Lid (Autodesk Fusion 360 design; units mm, degrees)
Autodesk Fusion 360 part; units mm, degrees
sketch "Sketch1" plane through (0, 0, 0) normal (0, 1, 0) x (1, 0, 0)
  line L0 (15.425, -22.7) -> (-15.425, -22.7)
  line L1 (-15.425, -22.7) -> (-15.425, 22.7)
  line L2 (-15.425, 22.7) -> (15.425, 22.7)
  line L3 (15.425, 22.7) -> (15.425, -22.7)
  line L4 (15.425, -22.7) -> (-15.425, 22.7) construction
  line L5 (-15.425, -22.7) -> (15.425, 22.7) construction
  line L6 (2, 18.7) -> (-2, 18.7)
  line L7 (-2, 18.7) -> (-2, 26.7)
  line L8 (-2, 26.7) -> (2, 26.7)
  line L9 (2, 26.7) -> (2, 18.7)
  line L10 (2, 18.7) -> (-2, 26.7) construction
  line L11 (-2, 18.7) -> (2, 26.7) construction
  line L12 (2, -26.7) -> (-2, -26.7)
  line L13 (-2, -26.7) -> (-2, -18.7)
  line L14 (-2, -18.7) -> (2, -18.7)
  line L15 (2, -18.7) -> (2, -26.7)
  line L16 (2, -26.7) -> (-2, -18.7) construction
  line L17 (-2, -26.7) -> (2, -18.7) construction
  point P0 (0, 22.7)
  point P1 (0, -22.7)
  dimension "d1" = 30.85
  dimension "d2" = 45.4
  dimension "d3" = 4
  dimension "d4" = 8
  dimension "d5" = 8
  dimension "d6" = 4
  constraint perpendicular L0 L1
  constraint parallel L0 L2
  constraint parallel L1 L3
  constraint horizontal L0
  constraint coincident L4 origin
  constraint coincident L5 origin
  constraint perpendicular L6 L7
  constraint parallel L6 L8
  constraint parallel L7 L9
  constraint horizontal L6
  constraint coincident L10 P0
  constraint coincident L11 P0
  constraint midpoint L2 P0
  constraint perpendicular L12 L13
  constraint parallel L12 L14
  constraint parallel L13 L15
  constraint horizontal L12
  constraint coincident L16 P1
  constraint coincident L17 P1
  constraint midpoint L0 P1
  measures "d1" distance of L1.end L2.end
  measures "d2" distance of L0.end L2.start L1
  measures "d3" distance of L7.end L8.end
  measures "d4" distance of L6.end L7.end
  measures "d5" distance of L12.end L13.end
  measures "d6" distance of L13.end L14.end
extrude "Extrude1" add sketch "Sketch1" along normal blind 3
sketch "Sketch2" plane through (0, 3, 0) normal (0, 1, 0) x (-1, 0, 0)
  line L0 (-15.425, 22.7) -> (-15.425, -22.7)
  line L1 (-15.425, -22.7) -> (-2, -22.7)
  line L2 (-2, -22.7) -> (-2, -26.7)
  line L3 (-2, -26.7) -> (2, -26.7)
  line L4 (2, -26.7) -> (2, -22.7)
  line L5 (2, -22.7) -> (15.425, -22.7)
  line L6 (15.425, -22.7) -> (15.425, 22.7)
  line L7 (15.425, 22.7) -> (2, 22.7)
  line L8 (2, 22.7) -> (2, 26.7)
  line L9 (2, 26.7) -> (-2, 26.7)
  line L10 (-2, 26.7) -> (-2, 22.7)
  line L11 (-2, 22.7) -> (-15.425, 22.7)
  line L12 (2, 24.7) -> (-12.6116, 24.7) construction
  line L13 (2, -24.7) -> (-12.7099, -24.7) construction
  line L14 (0, -26.7) -> (0, -20.5021) construction
  line L15 (0, 26.7) -> (0, 22.5765) construction
  circle A0 centre (0, 24.7) radius 1.375
  circle A1 centre (0, -24.7) radius 1.375
  dimension "d9" = 2.75
  dimension "d10" = 2.75
  constraint midpoint L8 L12.start
  constraint perpendicular L8 L12
  constraint midpoint L4 L13.start
  constraint perpendicular L4 L13
  constraint midpoint L3 L14.start
  constraint perpendicular L3 L14
  constraint midpoint L9 L15.start
  constraint perpendicular L12 L15
  constraint coincident L15 A0.centre
  constraint coincident L12 A0.centre
  constraint coincident L14 A1.centre
  constraint coincident L13 A1.centre
  measures "d9" diameter of A0
  measures "d10" diameter of A1
extrude "Extrude2" cut sketch "Sketch2" against normal up to surface (3 mm away) contours A0 | A1
fillet "Fillet1" radius 2.5 4 edges at (-15.425, 1.5, 22.7) (15.425, 1.5, 22.7) (15.425, 1.5, -22.7) (-15.425, 1.5, -22.7)
sketch "Sketch3" plane through (0, 3, 0) normal (0, 1, 0) x (-1, 0, 0)
  arc A0 (12.925, -22.7) -> (15.425, -20.2) centre (12.925, -20.2) ccw
  line L0 (15.425, -20.2) -> (15.425, 20.2)
  arc A1 (15.425, 20.2) -> (12.925, 22.7) centre (12.925, 20.2) ccw
  line L1 (12.925, 22.7) -> (2, 22.7)
  line L2 (2, 22.7) -> (2, 26.7)
  line L3 (2, 26.7) -> (-2, 26.7)
  line L4 (-2, 26.7) -> (-2, 22.7)
  line L5 (-2, 22.7) -> (-12.925, 22.7)
  arc A2 (-12.925, 22.7) -> (-15.425, 20.2) centre (-12.925, 20.2) ccw
  line L6 (-15.425, 20.2) -> (-15.425, -20.2)
  arc A3 (-15.425, -20.2) -> (-12.925, -22.7) centre (-12.925, -20.2) ccw
  line L7 (-12.925, -22.7) -> (-2, -22.7)
  line L8 (-2, -22.7) -> (-2, -26.7)
  line L9 (-2, -26.7) -> (2, -26.7)
  line L10 (2, -26.7) -> (2, -22.7)
  line L11 (2, -22.7) -> (12.925, -22.7)
  circle A4 centre (0, -24.7) radius 1.375
  circle A5 centre (0, 24.7) radius 1.375
  line L12 (-13.675, 21.2) -> (13.675, 21.2)
  line L13 (13.675, 21.2) -> (13.675, -21.2)
  line L14 (13.675, -21.2) -> (-13.675, -21.2)
  line L15 (-13.675, -21.2) -> (-13.675, 21.2)
  line L16 (-13.675, 21.2) -> (13.675, -21.2) construction
  line L17 (13.675, 21.2) -> (-13.675, -21.2) construction
  line L18 (-11.925, 19.2) -> (11.925, 19.2)
  line L19 (11.925, 19.2) -> (11.925, -19.2)
  line L20 (11.925, -19.2) -> (-11.925, -19.2)
  line L21 (-11.925, -19.2) -> (-11.925, 19.2)
  line L22 (-11.925, 19.2) -> (11.925, -19.2) construction
  line L23 (11.925, 19.2) -> (-11.925, -19.2) construction
  dimension "d14" = 42.4
  dimension "d15" = 27.35
  dimension "d16" = 23.85
  dimension "d17" = 38.4
  constraint perpendicular L12 L13
  constraint parallel L12 L14
  constraint parallel L13 L15
  constraint horizontal L12
  constraint coincident L16 origin
  constraint coincident L17 origin
  constraint perpendicular L18 L19
  constraint parallel L18 L20
  constraint parallel L19 L21
  constraint horizontal L18
  constraint coincident L22 origin
  constraint coincident L23 origin
  measures "d14" distance of L12.end L13.end
  measures "d15" distance of L13.end L14.end
  measures "d16" distance of L19.end L20.end
  measures "d17" distance of L18.end L19.end
extrude "Extrude3" cut sketch "Sketch3" against normal blind 1 contours L12 L13 L14 L15
fillet "Fillet2" radius 2.5 8 edges at (-13.675, 2.5, -21.2) (-11.925, 2.5, -19.2) (13.675, 2.5, -21.2) (11.925, 2.5, -19.2) (13.675, 2.5, 21.2) (11.925, 2.5, 19.2) (-13.675, 2.5, 21.2) (-11.925, 2.5, 19.2)
chamfer "Chamfer1" distance 4 angle 45 4 edges at (2, 1.5, 22.7) (-2, 1.5, 22.7) (2, 1.5, -22.7) (-2, 1.5, -22.7) tangent chain off
sketch "Sketch4" plane through (0, 0, 0) normal (0, -1, 0) x (1, 0, 0)
  circle A0 centre (0, -24.7) radius 1.375
  circle A1 centre (0, 24.7) radius 1.375
  arc A2 (-15.425, -20.2) -> (-12.925, -22.7) centre (-12.925, -20.2) ccw
  line L0 (-12.925, -22.7) -> (-6, -22.7)
  line L1 (-6, -22.7) -> (-2, -26.7)
  line L2 (-2, -26.7) -> (2, -26.7)
  line L3 (2, -26.7) -> (6, -22.7)
  line L4 (6, -22.7) -> (12.925, -22.7)
  arc A3 (12.925, -22.7) -> (15.425, -20.2) centre (12.925, -20.2) ccw
  line L5 (15.425, -20.2) -> (15.425, 20.2)
  arc A4 (15.425, 20.2) -> (12.925, 22.7) centre (12.925, 20.2) ccw
  line L6 (12.925, 22.7) -> (6, 22.7)
  line L7 (6, 22.7) -> (2, 26.7)
  line L8 (2, 26.7) -> (-2, 26.7)
  line L9 (-2, 26.7) -> (-6, 22.7)
  line L10 (-6, 22.7) -> (-12.925, 22.7)
  arc A5 (-12.925, 22.7) -> (-15.425, 20.2) centre (-12.925, 20.2) ccw
  line L11 (-15.425, 20.2) -> (-15.425, -20.2)
  line L12 (15.425, 18.7) -> (10.925, 18.7)
  line L13 (10.925, 18.7) -> (10.925, 26.7831)
  line L14 (10.925, 18.7) -> (10.925, 14.7)
  line L15 (10.925, 14.7) -> (15.425, 14.7086)
  line L16 (-8.925, 22.7) -> (-8.925, 18.7)
  line L17 (-8.925, 18.7) -> (-16.3729, 18.7)
  line L18 (-8.925, 18.7) -> (-8.925, 8.7)
  line L19 (-8.925, 8.7) -> (11, 8.7)
  line L20 (10.925, 14.7) -> (10.925, 2.1351)
  line L21 (-8.925, 18.7) -> (10.925, 18.7)
  dimension "d25" = 4.5
  dimension "d26" = 4
  dimension "d28" = 4
  dimension "d29" = 10
  constraint coincident L5 L12.start
  constraint perpendicular L6 L13
  constraint coincident L5 L15.end
  constraint coincident L10 L16.start
  constraint perpendicular L17 L18
  constraint perpendicular L18 L19
  constraint vertical L20
  constraint perpendicular L19 L20
  constraint perpendicular L14 L21
  measures "d25" distance of L12.start L12.end
  measures "d26" distance of L12.end L14.end
  measures "d28" distance of L16.start L16.end
  measures "d29" distance of L16.end L18.end
extrude "Extrude4" cut sketch "Sketch4" against normal up to surface (3 mm away) contours L14 L18 L19 L20 L21 | L5 L12 L14 L15
fillet "Fillet3" radius 1 4 edges at (-8.925, 1.5, 8.7) (10.925, 1.5, 8.7) (-8.925, 1.5, 18.7) (10.925, 1.5, 14.7)
fillet "Fillet4" radius 0.5 2 edges at (15.425, 1.5, 14.7086) (15.425, 1.5, 18.7)
fillet "Fillet5" radius 1 9 edges at (1.5, 3, 18.7) (-8.6321, 3, 18.4071) (-8.925, 3, 13.7) (-8.6321, 3, 8.9929) (1, 3, 8.7) (10.6321, 3, 8.9929) (10.925, 3, 11.701) (11.2172, 3, 14.4083) (11.924, 3, 14.7019)
sketch "Sketch5" plane through (15.425, 0, 0) normal (1, 0, 0) x (0, 0, -1)
  line L0 (-14.2076, 3) -> (-14.2076, 0)
  line L1 (-14.2076, 0) -> (20.2, 0)
  line L2 (20.2, 0) -> (20.2, 3)
  line L3 (20.2, 3) -> (-14.2076, 3)
  line L4 (20.2, 3) -> (-20.2, 3)
  line L5 (0, 0) -> (0, 3)
  line L6 (2, 3) -> (-2, 3)
  line L7 (-2, 3) -> (-2, -3)
  line L8 (-2, -3) -> (2, -3)
  line L9 (2, -3) -> (2, 3)
  line L10 (2, 3) -> (-2, -3) construction
  line L11 (-2, 3) -> (2, -3) construction
  dimension "d35" = 4
  dimension "d36" = 6
  constraint coincident L5.start origin
  constraint midpoint L4 L5.end
  constraint perpendicular L6 L7
  constraint parallel L6 L8
  constraint parallel L7 L9
  constraint horizontal L6
  constraint coincident L10 L5.start
  constraint coincident L11 L5.start
  measures "d35" distance of L7.end L8.end
  measures "d36" distance of L6.end L7.end
extrude "Extrude5" add sketch "Sketch5" along normal blind 3.75 contours L1 L3 L4 L5 L6 L7 | L1 L3 L4 L5 L6 L9
sketch "Sketch6" plane through (-15.425, 0, 0) normal (-1, 0, 0) x (0, 0, 1)
  line L0 (-20.2, 3) -> (-20.2, 0)
  line L1 (-20.2, 0) -> (20.2, 0)
  line L2 (20.2, 0) -> (20.2, 3)
  line L3 (20.2, 3) -> (-20.2, 3)
  line L4 (2, -0.518) -> (-2, -0.518)
  line L5 (-2, -0.518) -> (-2, 3.482)
  line L6 (-2, 3.482) -> (2, 3.482)
  line L7 (2, 3.482) -> (2, -0.518)
  line L8 (2, -0.518) -> (-2, 3.482) construction
  line L9 (-2, -0.518) -> (2, 3.482) construction
  point P0 (0, 1.482)
  dimension "d39" = 4
  dimension "d40" = 4
  constraint perpendicular L4 L5
  constraint parallel L4 L6
  constraint parallel L5 L7
  constraint horizontal L4
  constraint coincident L8 P0
  constraint coincident L9 P0
  measures "d39" distance of L4.end L5.end
  measures "d40" distance of L5.end L6.end
extrude "Extrude6" add sketch "Sketch6" along normal blind 3.75 contours L1 L3 L5 L7
chamfer "Chamfer2" distance 3.75 angle 45 4 edges at (15.425, 1.5, 2) (15.425, 1.5, -2) (-15.425, 1.5, -2) (-15.425, 1.5, 2) tangent chain off
sketch "Sketch7" plane through (0, 3, 0) normal (0, 1, 0) x (-1, 0, 0)
  arc A0 (-15.425, 19.2) -> (-14.925, 18.7) centre (-14.925, 19.2) ccw
  line L0 (-14.925, 18.7) -> (-13.675, 18.7)
  arc A1 (-11.175, 21.2) -> (-13.675, 18.7) centre (-11.175, 18.7) ccw
  line L1 (-11.175, 21.2) -> (11.175, 21.2)
  arc A2 (13.675, 18.7) -> (11.175, 21.2) centre (11.175, 18.7) ccw
  line L2 (13.675, 18.7) -> (13.675, -18.7)
  arc A3 (11.175, -21.2) -> (13.675, -18.7) centre (11.175, -18.7) ccw
  line L3 (11.175, -21.2) -> (-11.175, -21.2)
  arc A4 (-13.675, -18.7) -> (-11.175, -21.2) centre (-11.175, -18.7) ccw
  line L4 (-13.675, -18.7) -> (-13.675, 14.7052)
  line L5 (-13.675, 14.7052) -> (-14.924, 14.7076)
  arc A5 (-14.924, 14.7076) -> (-15.425, 14.2076) centre (-14.925, 14.2076) ccw
  line L6 (-15.425, 14.2076) -> (-15.425, 5.75)
  line L7 (-15.425, 5.75) -> (-19.175, 2)
  line L8 (-19.175, 2) -> (-19.175, -2)
  line L9 (-19.175, -2) -> (-15.425, -5.75)
  line L10 (-15.425, -5.75) -> (-15.425, -20.2)
  arc A6 (-15.425, -20.2) -> (-12.925, -22.7) centre (-12.925, -20.2) ccw
  line L11 (-12.925, -22.7) -> (-6, -22.7)
  line L12 (-6, -22.7) -> (-2, -26.7)
  line L13 (-2, -26.7) -> (2, -26.7)
  line L14 (2, -26.7) -> (6, -22.7)
  line L15 (6, -22.7) -> (12.925, -22.7)
  arc A7 (12.925, -22.7) -> (15.425, -20.2) centre (12.925, -20.2) ccw
  line L16 (15.425, -20.2) -> (15.425, -5.75)
  line L17 (15.425, -5.75) -> (19.175, -2)
  line L18 (19.175, -2) -> (19.175, 2)
  line L19 (19.175, 2) -> (15.425, 5.75)
  line L20 (15.425, 5.75) -> (15.425, 20.2)
  arc A8 (15.425, 20.2) -> (12.925, 22.7) centre (12.925, 20.2) ccw
  line L21 (12.925, 22.7) -> (6, 22.7)
  line L22 (6, 22.7) -> (2, 26.7)
  line L23 (2, 26.7) -> (-2, 26.7)
  line L24 (-2, 26.7) -> (-6, 22.7)
  line L25 (-6, 22.7) -> (-12.925, 22.7)
  arc A9 (-12.925, 22.7) -> (-15.425, 20.2) centre (-12.925, 20.2) ccw
  line L26 (-15.425, 20.2) -> (-15.425, 19.2)
  circle A10 centre (0, -24.7) radius 1.375
  circle A11 centre (0, 24.7) radius 1.375
  line L27 (19.175, 0) -> (17.175, 0)
  line L28 (-19.175, 0) -> (-17.175, 0)
  circle A12 centre (17.175, 0) radius 1.375
  circle A13 centre (-17.175, 0) radius 1.375
  dimension "d44" = 2
  dimension "d45" = 2
  dimension "d46" = 2.75
  dimension "d47" = 2.75
  constraint midpoint L18 L27.start
  constraint midpoint L8 L28.start
  constraint coincident L27.end A12.centre
  constraint coincident L28.end A13.centre
  measures "d44" distance of L27.start L27.end
  measures "d45" distance of L28.start L28.end
  measures "d46" diameter of A12
  measures "d47" diameter of A13
extrude "Extrude7" cut sketch "Sketch7" against normal up to surface (3 mm away) contours A12 | A13
